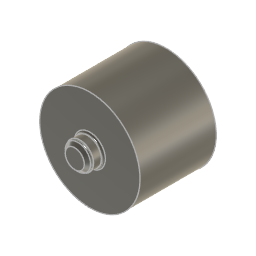
Quadruped (Autodesk Fusion 360 archive; units mm, degrees)
design "bassse"
part number: 2026-07-17-21-54-59-781
Autodesk Fusion 360 part; units mm, degrees
sketch "Sketch1" plane through (0, 0, 0) normal (0, 1, 0) x (1, 0, 0)
  circle A0 centre (0, 0) radius 25
  dimension "d2" = 50
  constraint coincident A0.centre origin
  measures "d2" diameter of A0
extrude "Extrude1" add sketch "Sketch1" along normal blind 38
sketch "Sketch2" plane through (0, 0, 0) normal (0, -1, 0) x (1, 0, 0)
  circle A0 centre (0, 0) radius 25
  circle A1 centre (0, 0) radius 6.75
  dimension "d5" = 13.5
  constraint coincident A0.centre A1.centre
  measures "d5" diameter of A1
extrude "Extrude2" add sketch "Sketch2" along normal blind 7.5 contours A1
sketch "Sketch3" plane through (0, 38, 0) normal (0, 1, 0) x (-1, 0, 0)
  circle A0 centre (0, 0) radius 25
  circle A1 centre (0, 0) radius 6.75
  dimension "d8" = 13.5
  constraint coincident A0.centre A1.centre
  measures "d8" diameter of A1
extrude "Extrude3" add sketch "Sketch3" along normal blind 7.5 contours A1
chamfer "Chamfer1" distance 2 angle 45 1 edges at (-6.2932, -7.5, -2.4409)
chamfer "Chamfer1" distance 2 angle 45 1 edges at (6.2932, 45.5, -2.4409)
fillet "Fillet1" radius 1.5 2 edges at (-6.2932, -5.5, -2.4409) (6.2932, 43.5, -2.4409)
fillet "Fillet2" radius 1 2 edges at (6.2932, 38, 2.4409) (-6.2932, 0, 2.4409)
